OPEN_LOUD_A0_E02 (Autodesk Fusion 360 design; units mm, degrees)
part number: 2026-11-09-20-55-57-870
part number: 2026-11-09-21-01-17-615
part number: 2026-11-09-21-01-17-676
part number: 2026-11-09-21-01-17-763
part number: 2026-11-09-21-01-17-864
part number: 2026-11-09-21-01-17-999
part number: 2026-11-09-21-01-18-154
part number: 2026-11-09-21-01-19-052
part number: 2026-11-09-21-01-19-319
part number: 2026-11-09-21-01-19-608
part number: 2026-11-09-21-01-19-923
part number: 2026-11-09-21-01-20-283
part number: 2026-11-09-21-01-21-563
part number: 2026-11-09-21-01-23-248
part number: 2026-11-09-21-01-23-714
Autodesk Fusion 360 part; units mm, degrees
ref_plane "Arbeitsebene1" through (0, 0, 0) normal (0, 0, 1) x (1, 0, 0) in component "Side_left"
sketch "Skizze1" plane through (0, 0, 0) normal (0, 0, 1) x (1, 0, 0) in component "Side_left"
  line L0 (0, 0) -> (12, 0)
  line L1 (12, 0) -> (12, 520)
  line L2 (12, 520) -> (0, 520)
  line L3 (0, 520) -> (0, 0)
  dimension "d51" = 12
  dimension "d52" = 520
  constraint coincident L0.start L3.end
  constraint horizontal L0
  constraint horizontal L2
  constraint vertical L1
  constraint vertical L3
  measures "d51" horizontal distance of L0.start L0.end
  measures "d52" vertical distance of L0.end L1.end
extrude "Side_left" add sketch "Skizze1" along normal blind 300 makes body 1 in component "Side_left"
ref_plane "Arbeitsebene1" through (0, 0, 0) normal (0, 0, 1) x (1, 0, 0) in component "Side_right"
sketch "Skizze1 (2)" plane through (0, 0, 0) normal (0, 0, 1) x (1, 0, 0) in component "Side_right"
  line L0 (318, 0) -> (330, 0)
  line L1 (330, 0) -> (330, 520)
  line L2 (330, 520) -> (318, 520)
  line L3 (318, 520) -> (318, 0)
  dimension "d57" = 318
  dimension "d58" = 12
  dimension "d59" = 520
  constraint horizontal origin L0.start
  constraint horizontal L0
  constraint horizontal L2
  constraint vertical L1
  constraint vertical L3
  measures "d57" horizontal distance of origin L0.start
  measures "d58" horizontal distance of L0.start L0.end
  measures "d59" vertical distance of L0.end L1.end
extrude "Side_right" add sketch "Skizze1 (2)" along normal blind 300 separate body makes body 2 in component "Side_right"
ref_plane "Arbeitsebene1" through (0, 0, 0) normal (0, 0, 1) x (1, 0, 0) in component "Bottom"
sketch "Skizze1 (3)" plane through (0, 0, 0) normal (0, 0, 1) x (1, 0, 0) in component "Bottom"
  line L0 (12, 0) -> (318, 0)
  line L1 (318, 0) -> (318, 12)
  line L2 (318, 12) -> (12, 12)
  line L3 (12, 12) -> (12, 0)
  dimension "d64" = 12
  dimension "d65" = 306
  dimension "d66" = 12
  constraint horizontal origin L0.start
  constraint horizontal L0
  constraint horizontal L2
  constraint vertical L1
  constraint vertical L3
  measures "d64" horizontal distance of origin L0.start
  measures "d65" horizontal distance of L0.start L0.end
  measures "d66" vertical distance of L0.end L1.end
extrude "Bottom" add sketch "Skizze1 (3)" along normal blind 300 separate body makes body 3 in component "Bottom"
ref_plane "Arbeitsebene1" through (0, 0, 0) normal (0, 0, 1) x (1, 0, 0) in component "Top"
sketch "Skizze1 (4)" plane through (0, 0, 0) normal (0, 0, 1) x (1, 0, 0) in component "Top"
  line L0 (12, 508) -> (318, 508)
  line L1 (318, 508) -> (318, 520)
  line L2 (318, 520) -> (12, 520)
  line L3 (12, 520) -> (12, 508)
  dimension "d71" = 12
  dimension "d72" = 508
  dimension "d73" = 306
  dimension "d74" = 12
  constraint horizontal L0
  constraint horizontal L2
  constraint vertical L1
  constraint vertical L3
  measures "d71" horizontal distance of origin L0.start
  measures "d72" vertical distance of origin L0.start
  measures "d73" horizontal distance of L0.start L0.end
  measures "d74" vertical distance of L0.end L1.end
extrude "Top" add sketch "Skizze1 (4)" along normal blind 300 separate body makes body 4 in component "Top"
ref_plane "Arbeitsebene1" through (0, 0, 0) normal (0, 0, 1) x (1, 0, 0) in component "Baffle"
sketch "Skizze1 (5)" plane through (0, 0, 0) normal (0, 0, 1) x (1, 0, 0) in component "Baffle"
  line L0 (12, 12) -> (318, 12)
  line L1 (318, 12) -> (318, 508)
  line L2 (318, 508) -> (12, 508)
  line L3 (12, 508) -> (12, 12)
  dimension "d79" = 12
  dimension "d80" = 12
  dimension "d81" = 306
  dimension "d82" = 496
  constraint horizontal L0
  constraint horizontal L2
  constraint vertical L1
  constraint vertical L3
  measures "d79" horizontal distance of origin L0.start
  measures "d80" vertical distance of origin L0.start
  measures "d81" horizontal distance of L0.start L0.end
  measures "d82" vertical distance of L0.end L1.end
extrude "Baffle" add sketch "Skizze1 (5)" along normal blind 12 separate body makes body 5 in component "Baffle"
ref_plane "Arbeitsebene1" through (0, 0, 288) normal (0, 0, 1) x (1, 0, 0) in component "Rear_removable"
sketch "Skizze1 (6)" plane through (0, 0, 288) normal (0, 0, 1) x (1, 0, 0) in component "Rear_removable"
  line L0 (12, 12) -> (318, 12)
  line L1 (318, 12) -> (318, 508)
  line L2 (318, 508) -> (12, 508)
  line L3 (12, 508) -> (12, 12)
  dimension "d87" = 12
  dimension "d88" = 12
  dimension "d89" = 306
  dimension "d90" = 496
  constraint horizontal L0
  constraint horizontal L2
  constraint vertical L1
  constraint vertical L3
  measures "d87" horizontal distance of origin L0.start
  measures "d88" vertical distance of origin L0.start
  measures "d89" horizontal distance of L0.start L0.end
  measures "d90" vertical distance of L0.end L1.end
extrude "Rear_removable" add sketch "Skizze1 (6)" along normal blind 12 separate body makes body 6 in component "Rear_removable"
ref_plane "Arbeitsebene2" through (0, 0, 0) normal (0, 0, 1) x (1, 0, 0) in component "Baffle"
sketch "Skizze2" plane through (0, 0, 0) normal (0, 0, 1) x (1, 0, 0) in component "Baffle"
  circle A0 centre (165, 244) radius 117.15
  dimension "d95" = 165
  dimension "d96" = 244
  dimension "d97" = 234.3
  measures "d95" horizontal distance of origin A0.centre
  measures "d96" vertical distance of origin A0.centre
  measures "d97" diameter of A0
extrude "LF_cut" cut sketch "Skizze2" along normal blind 12 bodies 5 in component "Baffle"
ref_plane "Arbeitsebene3" through (0, 0, 0) normal (0, 0, 1) x (1, 0, 0) in component "Baffle"
sketch "Skizze3" plane through (0, 0, 0) normal (0, 0, 1) x (1, 0, 0) in component "Baffle"
  circle A0 centre (165, 64) radius 48.9864
  dimension "d102" = 165
  dimension "d103" = 64
  dimension "d104" = 97.9728
  measures "d102" horizontal distance of origin A0.centre
  measures "d103" vertical distance of origin A0.centre
  measures "d104" diameter of A0
extrude "Port_cut" cut sketch "Skizze3" along normal blind 12 bodies 5 in component "Baffle"
ref_plane "Arbeitsebene4" through (0, 0, 0) normal (0, 0, 1) x (1, 0, 0) in component "Baffle"
sketch "Skizze4" plane through (0, 0, 0) normal (0, 0, 1) x (1, 0, 0) in component "Baffle"
  line L0 (113, 389) -> (217, 389)
  line L1 (217, 389) -> (217, 493)
  line L2 (217, 493) -> (113, 493)
  line L3 (113, 493) -> (113, 389)
  dimension "d109" = 113
  dimension "d110" = 389
  dimension "d111" = 104
  dimension "d112" = 104
  constraint horizontal L0
  constraint horizontal L2
  constraint vertical L1
  constraint vertical L3
  measures "d109" horizontal distance of origin L0.start
  measures "d110" vertical distance of origin L0.start
  measures "d111" horizontal distance of L0.start L0.end
  measures "d112" vertical distance of L0.end L1.end
extrude "Horn_cut" cut sketch "Skizze4" along normal blind 12 bodies 5 in component "Baffle"
sketch "Skizze5" plane through (0, 0, 0) normal (0, 0, 1) x (1, 0, 0) in component "Baffle"
  point P0 (286.9, 244)
  point P1 (251.1963, 330.1963)
  point P2 (165, 365.9)
  point P3 (78.8037, 330.1963)
  point P4 (43.1, 244)
  point P5 (78.8037, 157.8037)
  point P6 (165, 122.1)
  point P7 (251.1963, 157.8037)
ref_plane "Arbeitsebene1" through (0, 0, 171.6443) normal (0, 0, 1) x (1, 0, 0) in component "Service_partition"
sketch "Skizze1 (7)" plane through (0, 0, 171.6443) normal (0, 0, 1) x (1, 0, 0) in component "Service_partition"
  line L0 (12, 362) -> (318, 362)
  line L1 (318, 362) -> (318, 508)
  line L2 (318, 508) -> (12, 508)
  line L3 (12, 508) -> (12, 362)
  dimension "d117" = 12
  dimension "d118" = 362
  dimension "d119" = 306
  dimension "d120" = 146
  constraint horizontal L0
  constraint horizontal L2
  constraint vertical L1
  constraint vertical L3
  measures "d117" horizontal distance of origin L0.start
  measures "d118" vertical distance of origin L0.start
  measures "d119" horizontal distance of L0.start L0.end
  measures "d120" vertical distance of L0.end L1.end
extrude "Service_partition" add sketch "Skizze1 (7)" along normal blind 12 separate body makes body 7 in component "Service_partition"
ref_plane "Arbeitsebene1" through (0, 0, 171.6443) normal (0, 0, 1) x (1, 0, 0) in component "Service_floor"
sketch "Skizze1 (8)" plane through (0, 0, 171.6443) normal (0, 0, 1) x (1, 0, 0) in component "Service_floor"
  line L0 (12, 350) -> (318, 350)
  line L1 (318, 350) -> (318, 362)
  line L2 (318, 362) -> (12, 362)
  line L3 (12, 362) -> (12, 350)
  dimension "d125" = 12
  dimension "d126" = 350
  dimension "d127" = 306
  dimension "d128" = 12
  constraint horizontal L0
  constraint horizontal L2
  constraint vertical L1
  constraint vertical L3
  measures "d125" horizontal distance of origin L0.start
  measures "d126" vertical distance of origin L0.start
  measures "d127" horizontal distance of L0.start L0.end
  measures "d128" vertical distance of L0.end L1.end
extrude "Service_floor" add sketch "Skizze1 (8)" along normal blind 116.3557 separate body makes body 8 in component "Service_floor"
ref_plane "Arbeitsebene1" through (0, 0, 200) normal (0, 0, 1) x (1, 0, 0) in component "Brace_lower"
sketch "Skizze1 (9)" plane through (0, 0, 200) normal (0, 0, 1) x (1, 0, 0) in component "Brace_lower"
  line L0 (12, 140) -> (318, 140)
  line L1 (318, 140) -> (318, 160)
  line L2 (318, 160) -> (12, 160)
  line L3 (12, 160) -> (12, 140)
  dimension "d133" = 12
  dimension "d134" = 140
  dimension "d135" = 306
  dimension "d136" = 20
  constraint horizontal L0
  constraint horizontal L2
  constraint vertical L1
  constraint vertical L3
  measures "d133" horizontal distance of origin L0.start
  measures "d134" vertical distance of origin L0.start
  measures "d135" horizontal distance of L0.start L0.end
  measures "d136" vertical distance of L0.end L1.end
extrude "Brace_lower" add sketch "Skizze1 (9)" along normal blind 12 separate body makes body 9 in component "Brace_lower"
ref_plane "Arbeitsebene1" through (0, 0, 0) normal (0, 0, 1) x (1, 0, 0) in component "Port_round_candidate"
sketch "Skizze1 (10)" plane through (0, 0, 0) normal (0, 0, 1) x (1, 0, 0) in component "Port_round_candidate"
  circle A0 centre (165, 64) radius 48.4864
  circle A1 centre (165, 64) radius 45.4864
  dimension "d141" = 165
  dimension "d142" = 64
  dimension "d143" = 96.9728
  dimension "d144" = 90.9728
  constraint concentric A0 A1
  measures "d141" horizontal distance of origin A0.centre
  measures "d142" vertical distance of origin A0.centre
  measures "d143" diameter of A0
  measures "d144" diameter of A1
extrude "Port_tube" add sketch "Skizze1 (10)" along normal blind 161.4786 separate body makes body 10 in component "Port_round_candidate"
ref_plane "Arbeitsebene1" through (0, 0, -8) normal (0, 0, 1) x (1, 0, 0) in component "REF_Faital_10FE200_4ohm_DATASHEET_ENVELOPE"
sketch "Skizze1 (11)" plane through (0, 0, -8) normal (0, 0, 1) x (1, 0, 0) in component "REF_Faital_10FE200_4ohm_DATASHEET_ENVELOPE"
  circle A0 centre (165, 244) radius 128.4
  circle A1 centre (165, 244) radius 116.65
  dimension "d149" = 165
  dimension "d150" = 244
  dimension "d151" = 256.8
  dimension "d152" = 233.3
  constraint concentric A0 A1
  measures "d149" horizontal distance of origin A0.centre
  measures "d150" vertical distance of origin A0.centre
  measures "d151" diameter of A0
  measures "d152" diameter of A1
extrude "LF_flange_envelope" add sketch "Skizze1 (11)" along normal blind 8 separate body makes body 11 in component "REF_Faital_10FE200_4ohm_DATASHEET_ENVELOPE"
ref_plane "Arbeitsebene2" through (0, 0, 0) normal (0, 0, 1) x (1, 0, 0) in component "REF_Faital_10FE200_4ohm_DATASHEET_ENVELOPE"
sketch "Skizze2 (2)" plane through (0, 0, 0) normal (0, 0, 1) x (1, 0, 0) in component "REF_Faital_10FE200_4ohm_DATASHEET_ENVELOPE"
  circle A0 centre (165, 244) radius 115.9
  dimension "d157" = 165
  dimension "d158" = 244
  dimension "d159" = 231.8
  measures "d157" horizontal distance of origin A0.centre
  measures "d158" vertical distance of origin A0.centre
  measures "d159" diameter of A0
ref_plane "Arbeitsebene3" through (0, 0, 59.3) normal (0, 0, 1) x (1, 0, 0) in component "REF_Faital_10FE200_4ohm_DATASHEET_ENVELOPE"
sketch "Skizze3 (2)" plane through (0, 0, 59.3) normal (0, 0, 1) x (1, 0, 0) in component "REF_Faital_10FE200_4ohm_DATASHEET_ENVELOPE"
  circle A0 centre (165, 244) radius 57.65
  dimension "d162" = 165
  dimension "d163" = 244
  dimension "d164" = 115.3
  measures "d162" horizontal distance of origin A0.centre
  measures "d163" vertical distance of origin A0.centre
  measures "d164" diameter of A0
loft "Basket_clearance_frustum_NOT_SOLID_MATERIAL" add profiles "Skizze2 (2)", "Skizze3 (2)" section 1 section 2 separate body makes body 12 in component "REF_Faital_10FE200_4ohm_DATASHEET_ENVELOPE"
ref_plane "Arbeitsebene4" through (0, 0, 59.3) normal (0, 0, 1) x (1, 0, 0) in component "REF_Faital_10FE200_4ohm_DATASHEET_ENVELOPE"
sketch "Skizze4 (2)" plane through (0, 0, 59.3) normal (0, 0, 1) x (1, 0, 0) in component "REF_Faital_10FE200_4ohm_DATASHEET_ENVELOPE"
  circle A0 centre (165, 244) radius 57.65
  dimension "d167" = 165
  dimension "d168" = 244
  dimension "d169" = 115.3
  measures "d167" horizontal distance of origin A0.centre
  measures "d168" vertical distance of origin A0.centre
  measures "d169" diameter of A0
extrude "Magnet_envelope" add sketch "Skizze4 (2)" along normal blind 34.7 separate body makes body 13 in component "REF_Faital_10FE200_4ohm_DATASHEET_ENVELOPE"
ref_plane "Arbeitsebene1" through (0, 0, -5.5) normal (0, 0, 1) x (1, 0, 0) in component "REF_BC_ME10V3_DATASHEET_ENVELOPE"
sketch "Skizze1 (12)" plane through (0, 0, -5.5) normal (0, 0, 1) x (1, 0, 0) in component "REF_BC_ME10V3_DATASHEET_ENVELOPE"
  line L0 (99.75, 375.75) -> (230.25, 375.75)
  line L1 (230.25, 375.75) -> (230.25, 506.25)
  line L2 (230.25, 506.25) -> (99.75, 506.25)
  line L3 (99.75, 506.25) -> (99.75, 375.75)
  dimension "d174" = 99.75
  dimension "d175" = 375.75
  dimension "d176" = 130.5
  dimension "d177" = 130.5
  constraint horizontal L0
  constraint horizontal L2
  constraint vertical L1
  constraint vertical L3
  measures "d174" horizontal distance of origin L0.start
  measures "d175" vertical distance of origin L0.start
  measures "d176" horizontal distance of L0.start L0.end
  measures "d177" vertical distance of L0.end L1.end
extrude "Horn_flange_envelope" add sketch "Skizze1 (12)" along normal blind 5.5 separate body makes body 14 in component "REF_BC_ME10V3_DATASHEET_ENVELOPE"
ref_plane "Arbeitsebene2" through (0, 0, -5.5) normal (0, 0, 1) x (1, 0, 0) in component "REF_BC_ME10V3_DATASHEET_ENVELOPE"
sketch "Skizze2 (3)" plane through (0, 0, -5.5) normal (0, 0, 1) x (1, 0, 0) in component "REF_BC_ME10V3_DATASHEET_ENVELOPE"
  line L0 (113, 389) -> (217, 389)
  line L1 (217, 389) -> (217, 493)
  line L2 (217, 493) -> (113, 493)
  line L3 (113, 493) -> (113, 389)
  dimension "d182" = 113
  dimension "d183" = 389
  dimension "d184" = 104
  dimension "d185" = 104
  constraint horizontal L0
  constraint horizontal L2
  constraint vertical L1
  constraint vertical L3
  measures "d182" horizontal distance of origin L0.start
  measures "d183" vertical distance of origin L0.start
  measures "d184" horizontal distance of L0.start L0.end
  measures "d185" vertical distance of L0.end L1.end
extrude "Horn_mouth_open" cut sketch "Skizze2 (3)" along normal blind 5.5 bodies 14 in component "REF_BC_ME10V3_DATASHEET_ENVELOPE"
ref_plane "Arbeitsebene3" through (0, 0, 0) normal (0, 0, 1) x (1, 0, 0) in component "REF_BC_ME10V3_DATASHEET_ENVELOPE"
sketch "Skizze3 (3)" plane through (0, 0, 0) normal (0, 0, 1) x (1, 0, 0) in component "REF_BC_ME10V3_DATASHEET_ENVELOPE"
  line L0 (113, 389) -> (217, 389)
  line L1 (217, 389) -> (217, 493)
  line L2 (217, 493) -> (113, 493)
  line L3 (113, 493) -> (113, 389)
  dimension "d190" = 113
  dimension "d191" = 389
  dimension "d192" = 104
  dimension "d193" = 104
  constraint horizontal L0
  constraint horizontal L2
  constraint vertical L1
  constraint vertical L3
  measures "d190" horizontal distance of origin L0.start
  measures "d191" vertical distance of origin L0.start
  measures "d192" horizontal distance of L0.start L0.end
  measures "d193" vertical distance of L0.end L1.end
ref_plane "Arbeitsebene4" through (0, 0, 84.5) normal (0, 0, 1) x (1, 0, 0) in component "REF_BC_ME10V3_DATASHEET_ENVELOPE"
sketch "Skizze4 (3)" plane through (0, 0, 84.5) normal (0, 0, 1) x (1, 0, 0) in component "REF_BC_ME10V3_DATASHEET_ENVELOPE"
  circle A0 centre (165, 441) radius 12.5
  dimension "d196" = 165
  dimension "d197" = 441
  dimension "d198" = 25
  measures "d196" horizontal distance of origin A0.centre
  measures "d197" vertical distance of origin A0.centre
  measures "d198" diameter of A0
loft "Flare_clearance_ONLY_not_acoustic_surface" add profiles "Skizze3 (3)", "Skizze4 (3)" section 1 section 2 separate body makes body 15 in component "REF_BC_ME10V3_DATASHEET_ENVELOPE"
ref_plane "Arbeitsebene1" through (0, 0, 84.5) normal (0, 0, 1) x (1, 0, 0) in component "REF_BC_DE10_DATASHEET_ENVELOPE"
sketch "Skizze1 (13)" plane through (0, 0, 84.5) normal (0, 0, 1) x (1, 0, 0) in component "REF_BC_DE10_DATASHEET_ENVELOPE"
  circle A0 centre (165, 441) radius 45
  dimension "d201" = 165
  dimension "d202" = 441
  dimension "d203" = 90
  measures "d201" horizontal distance of origin A0.centre
  measures "d202" vertical distance of origin A0.centre
  measures "d203" diameter of A0
extrude "DE10_cylinder_envelope" add sketch "Skizze1 (13)" along normal blind 53 separate body makes body 16 in component "REF_BC_DE10_DATASHEET_ENVELOPE"
ref_plane "Arbeitsebene1" through (0, 0, 193.6443) normal (0, 0, 1) x (1, 0, 0) in component "RESERVE_amp_wiring_UNVERIFIED_no_mounting_holes"
sketch "Skizze1 (14)" plane through (0, 0, 193.6443) normal (0, 0, 1) x (1, 0, 0) in component "RESERVE_amp_wiring_UNVERIFIED_no_mounting_holes"
  line L0 (110, 372) -> (220, 372)
  line L1 (220, 372) -> (220, 482)
  line L2 (220, 482) -> (110, 482)
  line L3 (110, 482) -> (110, 372)
  dimension "d208" = 110
  dimension "d209" = 372
  dimension "d210" = 110
  dimension "d211" = 110
  constraint horizontal L0
  constraint horizontal L2
  constraint vertical L1
  constraint vertical L3
  measures "d208" horizontal distance of origin L0.start
  measures "d209" vertical distance of origin L0.start
  measures "d210" horizontal distance of L0.start L0.end
  measures "d211" vertical distance of L0.end L1.end
extrude "Amp_space_reserve" add sketch "Skizze1 (14)" along normal blind 40 separate body makes body 17 in component "RESERVE_amp_wiring_UNVERIFIED_no_mounting_holes"
sketch "Skizze6" plane through (0, 0, 0) normal (0, 0, -1) x (-1, 0, 0) in component "Baffle"
  line L0 (-217, 493) -> (-113, 493)
  line L1 (-113, 493) -> (-113, 389)
  line L2 (-113, 389) -> (-217, 389)
  line L3 (-217, 389) -> (-217, 493)
  circle A0 centre (-165, 64) radius 48.9864
  circle A1 centre (-165, 244) radius 117.15
  line L4 (-12, 12) -> (-12, 508)
  line L5 (-12, 508) -> (-318, 508)
  line L6 (-318, 508) -> (-318, 12)
  line L7 (-318, 12) -> (-12, 12)
sketch "Skizze2 (4)" plane through (0, 0, 300) normal (0, 0, 1) x (1, 0, 0) in component "Side_left"
  line L0 (0, 520) -> (0, 0)
  line L1 (0, 0) -> (12, 0)
  line L2 (12, 0) -> (12, 520)
  line L3 (12, 520) -> (0, 520)
sketch "Skizze2 (5)" plane through (0, 0, 300) normal (0, 0, 1) x (1, 0, 0) in component "Side_right"
  line L0 (318, 520) -> (318, 0)
  line L1 (318, 0) -> (330, 0)
  line L2 (330, 0) -> (330, 520)
  line L3 (330, 520) -> (318, 520)
sketch "Skizze2 (6)" plane through (0, 0, 300) normal (0, 0, 1) x (1, 0, 0) in component "Bottom"
  line L0 (12, 12) -> (12, 0)
  line L1 (12, 0) -> (318, 0)
  line L2 (318, 0) -> (318, 12)
  line L3 (318, 12) -> (12, 12)
sketch "Skizze2 (7)" plane through (0, 0, 300) normal (0, 0, 1) x (1, 0, 0) in component "Top"
  line L0 (12, 520) -> (12, 508)
  line L1 (12, 508) -> (318, 508)
  line L2 (318, 508) -> (318, 520)
  line L3 (318, 520) -> (12, 520)
sketch "Skizze2 (8)" plane through (0, 0, 300) normal (0, 0, 1) x (1, 0, 0) in component "Rear_removable"
  line L0 (12, 508) -> (12, 12)
  line L1 (12, 12) -> (318, 12)
  line L2 (318, 12) -> (318, 508)
  line L3 (318, 508) -> (12, 508)
sketch "Skizze2 (9)" plane through (0, 0, 183.6443) normal (0, 0, 1) x (1, 0, 0) in component "Service_partition"
  line L0 (12, 508) -> (12, 362)
  line L1 (12, 362) -> (318, 362)
  line L2 (318, 362) -> (318, 508)
  line L3 (318, 508) -> (12, 508)
sketch "Skizze2 (10)" plane through (0, 0, 288) normal (0, 0, 1) x (1, 0, 0) in component "Service_floor"
  line L0 (12, 362) -> (12, 350)
  line L1 (12, 350) -> (318, 350)
  line L2 (318, 350) -> (318, 362)
  line L3 (318, 362) -> (12, 362)
sketch "Skizze2 (11)" plane through (0, 0, 212) normal (0, 0, 1) x (1, 0, 0) in component "Brace_lower"
  line L0 (12, 160) -> (12, 140)
  line L1 (12, 140) -> (318, 140)
  line L2 (318, 140) -> (318, 160)
  line L3 (318, 160) -> (12, 160)
sketch "Skizze3 (4)" plane through (12, 0, 0) normal (1, 0, 0) x (0, 1, 0) in component "Side_left"
  line L0 (0, 0) -> (520, 0)
  line L1 (520, 0) -> (520, 300)
  line L2 (520, 300) -> (0, 300)
  line L3 (0, 300) -> (0, 0)
sketch "Skizze3 (5)" plane through (330, 0, 0) normal (1, 0, 0) x (0, 1, 0) in component "Side_right"
  line L0 (0, 0) -> (520, 0)
  line L1 (520, 0) -> (520, 300)
  line L2 (520, 300) -> (0, 300)
  line L3 (0, 300) -> (0, 0)
sketch "Skizze3 (6)" plane through (0, 12, 0) normal (0, 1, 0) x (-1, 0, 0) in component "Bottom"
  line L0 (-318, 0) -> (-12, 0)
  line L1 (-12, 0) -> (-12, 300)
  line L2 (-12, 300) -> (-318, 300)
  line L3 (-318, 300) -> (-318, 0)
sketch "Skizze3 (7)" plane through (0, 520, 0) normal (0, 1, 0) x (-1, 0, 0) in component "Top"
  line L0 (-318, 0) -> (-12, 0)
  line L1 (-12, 0) -> (-12, 300)
  line L2 (-12, 300) -> (-318, 300)
  line L3 (-318, 300) -> (-318, 0)
sketch "Skizze3 (8)" plane through (0, 0, 300) normal (0, 0, 1) x (1, 0, 0) in component "Rear_removable"
  line L0 (12, 508) -> (12, 12)
  line L1 (12, 12) -> (318, 12)
  line L2 (318, 12) -> (318, 508)
  line L3 (318, 508) -> (12, 508)
sketch "Skizze3 (9)" plane through (0, 0, 183.6443) normal (0, 0, 1) x (1, 0, 0) in component "Service_partition"
  line L0 (12, 508) -> (12, 362)
  line L1 (12, 362) -> (318, 362)
  line L2 (318, 362) -> (318, 508)
  line L3 (318, 508) -> (12, 508)
sketch "Skizze3 (10)" plane through (0, 362, 0) normal (0, 1, 0) x (-1, 0, 0) in component "Service_floor"
  line L0 (-318, 171.6443) -> (-12, 171.6443)
  line L1 (-12, 171.6443) -> (-12, 288)
  line L2 (-12, 288) -> (-318, 288)
  line L3 (-318, 288) -> (-318, 171.6443)
sketch "Skizze3 (11)" plane through (0, 0, 212) normal (0, 0, 1) x (1, 0, 0) in component "Brace_lower"
  line L0 (12, 160) -> (12, 140)
  line L1 (12, 140) -> (318, 140)
  line L2 (318, 140) -> (318, 160)
  line L3 (318, 160) -> (12, 160)
component "Side_left" placed x (1, 0, 0) y (0, 1, 0) z (0, 0, 1) at (0, 0, 0)
component "Side_right" placed x (1, 0, 0) y (0, 1, 0) z (0, 0, 1) at (0, 0, 0)
component "Bottom" placed x (1, 0, 0) y (0, 1, 0) z (0, 0, 1) at (0, 0, 0)
component "Top" placed x (1, 0, 0) y (0, 1, 0) z (0, 0, 1) at (0, 0, 0)
component "Baffle" placed x (1, 0, 0) y (0, 1, 0) z (0, 0, 1) at (0, 0, 0)
component "Rear_removable" placed x (1, 0, 0) y (0, 1, 0) z (0, 0, 1) at (0, 0, 0)
component "Service_partition" placed x (1, 0, 0) y (0, 1, 0) z (0, 0, 1) at (0, 0, 0)
component "Service_floor" placed x (1, 0, 0) y (0, 1, 0) z (0, 0, 1) at (0, 0, 0)
component "Brace_lower" placed x (1, 0, 0) y (0, 1, 0) z (0, 0, 1) at (0, 0, 0)
component "Port_round_candidate" placed x (1, 0, 0) y (0, 1, 0) z (0, 0, 1) at (0, 0, 0)
component "REF_Faital_10FE200_4ohm_DATASHEET_ENVELOPE" placed x (1, 0, 0) y (0, 1, 0) z (0, 0, 1) at (0, 0, 0)
component "REF_BC_ME10V3_DATASHEET_ENVELOPE" placed x (1, 0, 0) y (0, 1, 0) z (0, 0, 1) at (0, 0, 0)
component "REF_BC_DE10_DATASHEET_ENVELOPE" placed x (1, 0, 0) y (0, 1, 0) z (0, 0, 1) at (0, 0, 0)
component "RESERVE_amp_wiring_UNVERIFIED_no_mounting_holes" placed x (1, 0, 0) y (0, 1, 0) z (0, 0, 1) at (0, 0, 0)
equation "height = 520 mm" comment "report:p12; envelope_not_CAD"
equation "width = 330 mm" comment "report:p12; envelope_not_CAD"
equation "depth = 300 mm" comment "report:p12; envelope_not_CAD"
equation "wall = 12 mm" comment "report:p12; design_candidate"
equation "lf_outer = 256.8 mm" comment "S31; design_candidate"
equation "lf_cutout = 233.3 mm" comment "S31; design_candidate"
equation "lf_depth = 102 mm" comment "S31; design_candidate"
equation "lf_flange = 8 mm" comment "S31; design_candidate"
equation "lf_pcd = 243.8 mm" comment "S31; design_candidate"
equation "lf_magnet_d = 115.3 mm" comment "S31:drawing_4; design_candidate"
equation "lf_magnet_depth = 34.7 mm" comment "S31:drawing_4; design_candidate"
equation "lf_basket_d = 231.8 mm" comment "S31:drawing_4; design_candidate"
equation "lf_hole_d = 5.7 mm" comment "S31:drawing_4; design_candidate"
equation "horn_width = 130.5 mm" comment "S50; design_candidate"
equation "horn_depth = 90 mm" comment "S50; design_candidate"
equation "horn_cutout = 104 mm" comment "S50:cutout_shape_to_verify; design_candidate"
equation "horn_throat = 25 mm" comment "S50; design_candidate"
equation "horn_flange = 5.5 mm" comment "engineering:E02; assumed_flange_not_manufacturer"
equation "hf_diameter = 90 mm" comment "S48; design_candidate"
equation "hf_depth = 53 mm" comment "S48; design_candidate"
equation "lf_y = 244 mm" comment "engineering:E02; design_candidate"
equation "horn_y = 441 mm" comment "engineering:E02; design_candidate"
equation "port_y = 64 mm" comment "engineering:E02; design_candidate"
equation "port_wall = 3 mm" comment "engineering:E02; design_candidate"
equation "service_floor_y = 350 mm" comment "engineering:E02; design_candidate"
equation "brace_y = 140 mm" comment "engineering:E02; design_candidate"
equation "brace_z = 200 mm" comment "engineering:E02; design_candidate"
equation "brace_height = 20 mm" comment "engineering:E02; design_candidate"
equation "baffle_clearance = 0.5 mm" comment "engineering:E02; radial_manufacturing_allowance"
equation "amp_reserve_width = 110 mm" comment "engineering:E02; unverified_installation_reserve_not_board_dimension"
equation "amp_reserve_height = 110 mm" comment "engineering:E02; unverified_installation_reserve_not_board_dimension"
equation "amp_reserve_depth = 40 mm" comment "engineering:E02; unverified_installation_reserve_not_board_dimension"
equation "target_net = 34000000 mm^3" comment "report:p7"
equation "port_area = 6500 mm^2" comment "report:p7"
equation "port_length = 161.47860433 mm" comment "derived Helmholtz and equivalent-round end correction; prototype tune"
equation "lf_displacement = 600000 mm^3" comment "manufacturer occupied air volume, not solid clearance-envelope volume"
equation "horn_displacement = 150000 mm^3" comment "manufacturer horn volume"
equation "port_d = 90.9728368293 mm" comment "derived in Python; Fusion area-reference scaling workaround"
equation "service_z = 171.64431914 mm" comment "derived net-volume budget in Python; regenerate after dimensional changes"
equation "inner_width = width - 2 * wall" comment "E02 concept"
equation "inner_height = height - 2 * wall" comment "E02 concept"
equation "inner_depth = depth - 2 * wall" comment "E02 concept"
equation "port_outer_d = port_d + 2 * port_wall" comment "E02 concept"
equation "gross_internal = inner_width * inner_height * inner_depth" comment "E02 concept"
equation "port_displacement = PI / 4 * port_outer_d ^ 2 * ( port_length - wall )" comment "E02 concept"
equation "hf_displacement = PI / 4 * hf_diameter ^ 2 * hf_depth" comment "E02 concept"
equation "brace_displacement = inner_width * brace_height * wall" comment "E02 concept"
equation "service_reserve = inner_width * ( height - wall - service_floor_y ) * ( depth - wall - service_z )" comment "E02 concept"
equation "d51 = wall"
equation "d52 = height"
equation "d53 = depth"
equation "d57 = width - wall"
equation "d58 = wall"
equation "d59 = height"
equation "d60 = depth"
equation "d64 = wall"
equation "d65 = inner_width"
equation "d66 = wall"
equation "d67 = depth"
equation "d71 = wall"
equation "d72 = height - wall"
equation "d73 = inner_width"
equation "d74 = wall"
equation "d75 = depth"
equation "d79 = wall"
equation "d80 = wall"
equation "d81 = inner_width"
equation "d82 = inner_height"
equation "d83 = wall"
equation "d85 = depth - wall"
equation "d87 = wall"
equation "d88 = wall"
equation "d89 = inner_width"
equation "d90 = inner_height"
equation "d91 = wall"
equation "d95 = width / 2"
equation "d96 = lf_y"
equation "d97 = lf_cutout + 2 * baffle_clearance"
equation "d98 = wall"
equation "d102 = width / 2"
equation "d103 = port_y"
equation "d104 = port_outer_d + 2 * baffle_clearance"
equation "d105 = wall"
equation "d109 = ( width - horn_cutout ) / 2"
equation "d110 = horn_y - horn_cutout / 2"
equation "d111 = horn_cutout"
equation "d112 = horn_cutout"
equation "d113 = wall"
equation "d115 = service_z"
equation "d117 = wall"
equation "d118 = service_floor_y + wall"
equation "d119 = inner_width"
equation "d120 = height - wall - service_floor_y - wall"
equation "d121 = wall"
equation "d123 = service_z"
equation "d125 = wall"
equation "d126 = service_floor_y"
equation "d127 = inner_width"
equation "d128 = wall"
equation "d129 = depth - wall - service_z"
equation "d131 = brace_z"
equation "d133 = wall"
equation "d134 = brace_y"
equation "d135 = inner_width"
equation "d136 = brace_height"
equation "d137 = wall"
equation "d141 = width / 2"
equation "d142 = port_y"
equation "d143 = port_outer_d"
equation "d144 = port_d"
equation "d145 = port_length"
equation "d147 = -lf_flange"
equation "d149 = width / 2"
equation "d150 = lf_y"
equation "d151 = lf_outer"
equation "d152 = lf_cutout"
equation "d153 = lf_flange"
equation "d157 = width / 2"
equation "d158 = lf_y"
equation "d159 = lf_basket_d"
equation "d160 = lf_depth - lf_flange - lf_magnet_depth"
equation "d162 = width / 2"
equation "d163 = lf_y"
equation "d164 = lf_magnet_d"
equation "d165 = lf_depth - lf_flange - lf_magnet_depth"
equation "d167 = width / 2"
equation "d168 = lf_y"
equation "d169 = lf_magnet_d"
equation "d170 = lf_magnet_depth"
equation "d172 = -horn_flange"
equation "d174 = ( width - horn_width ) / 2"
equation "d175 = horn_y - horn_width / 2"
equation "d176 = horn_width"
equation "d177 = horn_width"
equation "d178 = horn_flange"
equation "d180 = -horn_flange"
equation "d182 = ( width - horn_cutout ) / 2"
equation "d183 = horn_y - horn_cutout / 2"
equation "d184 = horn_cutout"
equation "d185 = horn_cutout"
equation "d186 = horn_flange"
equation "d190 = ( width - horn_cutout ) / 2"
equation "d191 = horn_y - horn_cutout / 2"
equation "d192 = horn_cutout"
equation "d193 = horn_cutout"
equation "d194 = horn_depth - horn_flange"
equation "d196 = width / 2"
equation "d197 = horn_y"
equation "d198 = horn_throat"
equation "d199 = horn_depth - horn_flange"
equation "d201 = width / 2"
equation "d202 = horn_y"
equation "d203 = hf_diameter"
equation "d204 = hf_depth"
equation "d206 = service_z + wall + 10 mm"
equation "d208 = ( width - amp_reserve_width ) / 2"
equation "d209 = service_floor_y + wall + 10 mm"
equation "d210 = amp_reserve_width"
equation "d211 = amp_reserve_height"
equation "d212 = amp_reserve_depth"
named bodies: "Side_left", "Side_right", "Bottom", "Top", "Baffle", "Rear_removable", "Service_partition", "Service_floor", "Brace_lower", "Port_tube", "LF_flange_envelope", "Magnet_envelope", "Horn_flange_envelope", "DE10_cylinder_envelope", "Amp_space_reserve"
